Autodesk Fusion 360 part; units mm, degrees
(part 3 of 3)
component "LEG | Continuous centred upper enclosure" placed x (-0.286788, -0.496732, 0.819152) y (0.866025, -0.5, 0) z (0.409576, 0.709406, 0.573576) at (-47, -81.4064, -12)
component "LEG | Full red front service panel" placed x (-0.286788, -0.496732, 0.819152) y (0.866025, -0.5, 0) z (0.409576, 0.709406, 0.573576) at (-47, -81.4064, -12)
component "LEG | Centred tapered lower arm" placed x (-0.154508, -0.267617, -0.951057) y (0.866025, -0.5, 0) z (-0.475528, -0.823639, 0.309017) at (-61.913, -107.2364, 30.5959)
component "FOOT | Centred soft toe boot" placed x (-0.154508, -0.267617, -0.951057) y (0.866025, -0.5, 0) z (-0.475528, -0.823639, 0.309017) at (-61.913, -107.2364, 30.5959)
component "KEEP-OUT | YawReserve · actuator not selected" placed x (-0.5, -0.866025, 0) y (0.866025, -0.5, 0) z (0, 0, 1) at (-24.5, -42.4352, 0)
component "KEEP-OUT | HipReserve · actuator not selected" placed x (-0.286788, -0.496732, 0.819152) y (0.866025, -0.5, 0) z (0.409576, 0.709406, 0.573576) at (-47, -81.4064, -12)
component "KEEP-OUT | KneeReserve · actuator not selected" placed x (-0.286788, -0.496732, 0.819152) y (0.866025, -0.5, 0) z (0.409576, 0.709406, 0.573576) at (-47, -81.4064, -12)
component "LEG | Centred proximal clevis" placed x (0.5, -0.866025, 0) y (0.866025, 0.5, 0) z (0, 0, 1) at (24.5, -42.4352, 0)
component "LEG | Continuous centred upper enclosure" placed x (0.286788, -0.496732, 0.819152) y (0.866025, 0.5, 0) z (-0.409576, 0.709406, 0.573576) at (47, -81.4064, -12)
component "LEG | Full red front service panel" placed x (0.286788, -0.496732, 0.819152) y (0.866025, 0.5, 0) z (-0.409576, 0.709406, 0.573576) at (47, -81.4064, -12)
component "LEG | Centred tapered lower arm" placed x (0.154508, -0.267617, -0.951057) y (0.866025, 0.5, 0) z (0.475528, -0.823639, 0.309017) at (61.913, -107.2364, 30.5959)
component "FOOT | Centred soft toe boot" placed x (0.154508, -0.267617, -0.951057) y (0.866025, 0.5, 0) z (0.475528, -0.823639, 0.309017) at (61.913, -107.2364, 30.5959)
component "KEEP-OUT | YawReserve · actuator not selected" placed x (0.5, -0.866025, 0) y (0.866025, 0.5, 0) z (0, 0, 1) at (24.5, -42.4352, 0)
component "KEEP-OUT | HipReserve · actuator not selected" placed x (0.286788, -0.496732, 0.819152) y (0.866025, 0.5, 0) z (-0.409576, 0.709406, 0.573576) at (47, -81.4064, -12)
component "KEEP-OUT | KneeReserve · actuator not selected" placed x (0.286788, -0.496732, 0.819152) y (0.866025, 0.5, 0) z (-0.409576, 0.709406, 0.573576) at (47, -81.4064, -12)
component "CORE | BatteryReserve" placed x (1, 0, 0) y (0, 1, 0) z (0, 0, 1) at (0, 0, 0)
component "CORE | RegulatorReserve" placed x (0.866025, 0.5, 0) y (-0.5, 0.866025, 0) z (0, 0, 1) at (0, 0, 0)
component "CORE | ESP32Reserve" placed x (1, 0, 0) y (0, 1, 0) z (0, 0, 1) at (0, 0, 0)
component "SERVICE HARDWARE | Core lid 1" placed x (1, 0, 0) y (0, 1, 0) z (0, 0, 1) at (0, 0, 0)
component "SERVICE HARDWARE | Core lid 2" placed x (1, 0, 0) y (0, 1, 0) z (0, 0, 1) at (0, 0, 0)
component "SERVICE HARDWARE | Core lid 3" placed x (1, 0, 0) y (0, 1, 0) z (0, 0, 1) at (0, 0, 0)
component "SERVICE HARDWARE | Core lid 4" placed x (1, 0, 0) y (0, 1, 0) z (0, 0, 1) at (0, 0, 0)
component "SERVICE HARDWARE | Cassette 1" placed x (1, 0, 0) y (0, 1, 0) z (0, 0, 1) at (0, 0, 0)
component "SERVICE HARDWARE | Cassette 2" placed x (1, 0, 0) y (0, 1, 0) z (0, 0, 1) at (0, 0, 0)
component "SERVICE HARDWARE | L1 upper cover" placed x (0.573576, 0, 0.819152) y (0, 1, 0) z (-0.819152, 0, 0.573576) at (94, 0, -12)
component "SERVICE HARDWARE | L2 upper cover" placed x (0.286788, 0.496732, 0.819152) y (-0.866025, 0.5, 0) z (-0.409576, -0.709406, 0.573576) at (47, 81.4064, -12)
component "SERVICE HARDWARE | L3 upper cover" placed x (-0.286788, 0.496732, 0.819152) y (-0.866025, -0.5, 0) z (0.409576, -0.709406, 0.573576) at (-47, 81.4064, -12)
component "SERVICE HARDWARE | L4 upper cover" placed x (-0.573576, 0, 0.819152) y (0, -1, 0) z (0.819152, 0, 0.573576) at (-94, 0, -12)
component "SERVICE HARDWARE | L5 upper cover" placed x (-0.286788, -0.496732, 0.819152) y (0.866025, -0.5, 0) z (0.409576, 0.709406, 0.573576) at (-47, -81.4064, -12)
component "SERVICE HARDWARE | L6 upper cover" placed x (0.286788, -0.496732, 0.819152) y (0.866025, 0.5, 0) z (-0.409576, 0.709406, 0.573576) at (47, -81.4064, -12)
equation "hx_yaw_radius = 49.0 mm" comment "Generator reference; exact actuator interfaces intentionally pending"
equation "hx_coxa = 45.0 mm" comment "Generator reference; exact actuator interfaces intentionally pending"
equation "hx_femur = 52.0 mm" comment "Generator reference; exact actuator interfaces intentionally pending"
equation "hx_tibia = 93.0 mm" comment "Generator reference; exact actuator interfaces intentionally pending"
equation "hx_shoulder_z = -12.0 mm" comment "Generator reference; exact actuator interfaces intentionally pending"
equation "hx_femur_angle = 55.0 deg" comment "Generator reference; exact actuator interfaces intentionally pending"
equation "hx_tibia_angle = -72.0 deg" comment "Generator reference; exact actuator interfaces intentionally pending"
equation "hx_plate = 3.0 mm" comment "Generator reference; exact actuator interfaces intentionally pending"
equation "hx_foot_lateral = 0.0 mm" comment "Generator reference; exact actuator interfaces intentionally pending"
named bodies: "CoreTub", "CoreLid", "ElectronicsCassette", "CoxaCarrier", "FemurCarrier", "FemurCheek", "Tibia", "FootPad"
